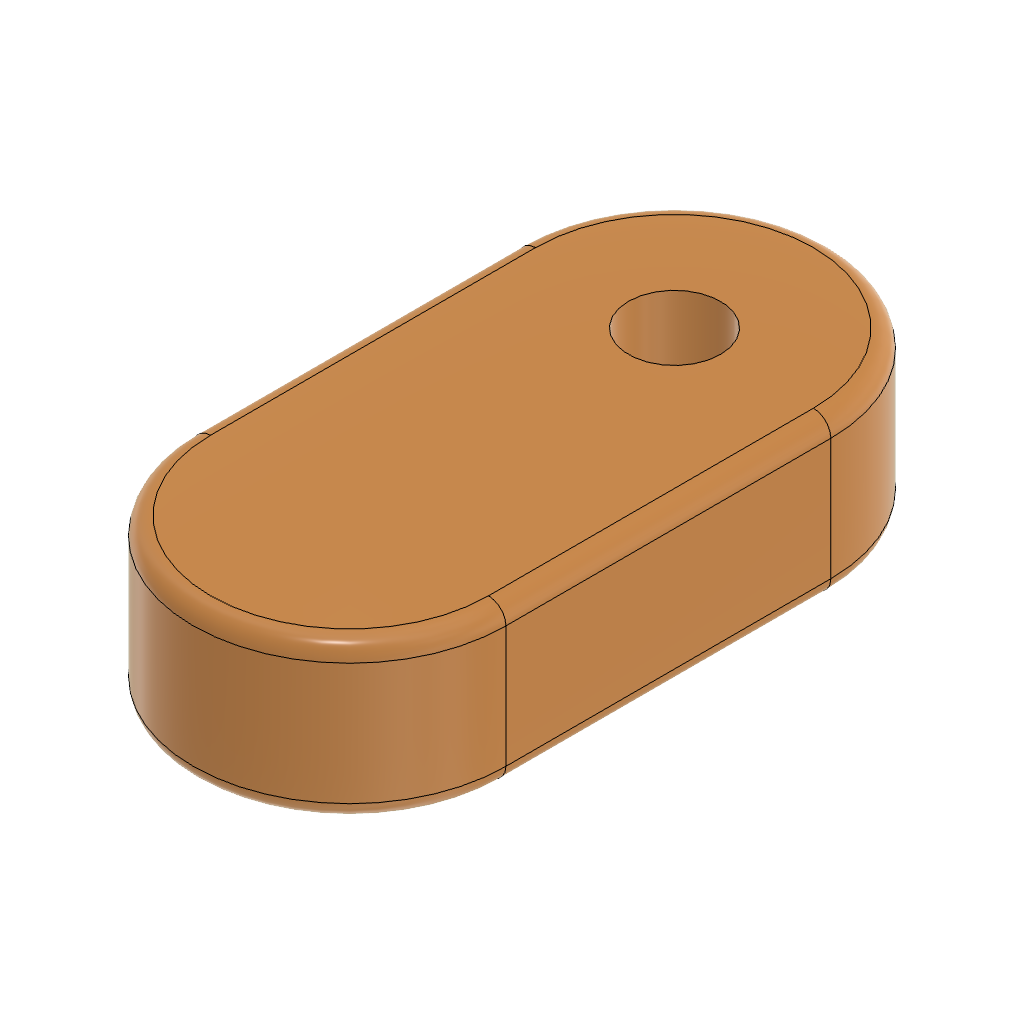
crank_outer (Autodesk Fusion 360 design; units mm, degrees)
part number: 2026-09-19-23-47-10-584
Autodesk Fusion 360 part; units mm, degrees
sketch "Sketch1" plane through (0, 0, 0) normal (0, 0, 1) x (1, 0, 0)
  line L0 (-3.85, -3.85) -> (3.85, -3.85)
  line L1 (3.85, -3.85) -> (3.85, 3.85)
  line L2 (3.85, 3.85) -> (-3.85, 3.85)
  line L3 (-3.85, 3.85) -> (-3.85, -3.85)
  line L4 (-3.85, -3.85) -> (3.85, 3.85) construction
  line L5 (3.85, -3.85) -> (-3.85, 3.85) construction
  circle A0 centre (0, 18.7) radius 9
  circle A1 centre (0, 0) radius 9
  line L6 (9, 0) -> (-9, 0)
  line L7 (-9, 0) -> (9, 0)
  line L8 (9, 0) -> (9, 18.7)
  line L9 (9, 18.7) -> (-9, 18.7)
  line L10 (-9, 18.7) -> (-9, 0)
  line L11 (-9, 0) -> (9, 18.7) construction
  line L12 (9, 0) -> (-9, 18.7) construction
  circle A2 centre (0, 18.7) radius 2.65
  point P0 (0, 18.7)
  point P1 (0, 9.35)
  dimension "d1" = 7.7
  dimension "d2" = 7.7
  dimension "d5" = 18.7
  dimension "d7" = 18
  dimension "d8" = 18
  dimension "d12" = 18
  dimension "d16" = 5.3
  dimension "d23" = 18.7
  constraint horizontal L0
  constraint perpendicular L0 L1
  constraint parallel L0 L2
  constraint parallel L1 L3
  constraint coincident L4 A1.centre
  constraint coincident L5 A1.centre
  constraint coincident A1.centre origin
  constraint coincident P0 A0.centre
  constraint horizontal L6
  constraint coincident A1 L6.end
  constraint horizontal L7
  constraint perpendicular L7 L8
  constraint parallel L7 L9
  constraint parallel L8 L10
  constraint coincident L11 P1
  constraint coincident L12 P1
  constraint vertical A1.centre A0.centre
  constraint coincident A0 L8.end
  measures "d1" distance of L1.end L2.end
  measures "d2" distance of L0.end L1.end
  measures "d5" vertical distance of A1.centre P0
  measures "d7" diameter of A0
  measures "d8" diameter of A1
  measures "d12" distance of L8.end L9.end
  measures "d16" diameter of A2
  measures "d23" distance of L6.start L8.end
extrude "Extrude2" add sketch "Sketch1" along normal blind 9 contours L0 L1 L3 A1 L6 L7 | L1 L2 L3 A1 L6 L7 | A0 A1 L8 L10 | A0 L9 A2 | A0 L9 A2 | L9 A2 | L9 A2
extrude "Extrude3" cut sketch "Sketch1" along normal blind 15 contours L9 A2 | L9 A2
sketch "Sketch2" plane through (0, 0, 9) normal (0, 0, 1) x (-1, 0, 0)
  circle A0 centre (0, -18.7) radius 2.65
  line L0 (3.85, 3.85) -> (3.85, -3.85)
  line L1 (3.85, -3.85) -> (-3.85, -3.85)
  line L2 (-3.85, -3.85) -> (-3.85, 3.85)
  line L3 (-3.85, 3.85) -> (3.85, 3.85)
  line L4 (9, -18.7) -> (9, 0)
  arc A1 (9, 0) -> (-9, 0) centre (0, 0) ccw
  line L5 (-9, 0) -> (-9, -18.7)
  arc A2 (-9, -18.7) -> (9, -18.7) centre (0, -18.7) ccw
  line L6 (-3.85, 3.85) -> (3.85, 3.85)
  line L7 (3.85, 3.85) -> (3.85, -3.85)
  line L8 (3.85, -3.85) -> (-3.85, -3.85)
  line L9 (-3.85, -3.85) -> (-3.85, 3.85)
  constraint horizontal L6
  constraint vertical L7
  constraint horizontal L8
  constraint vertical L9
  constraint coincident L0.end L1.start
  constraint coincident L2.end L3.start
extrude "Extrude4" add sketch "Sketch2" against normal blind 2 contours L0 L1 L2 L3 L6 L7 L8 L9
fillet "Fillet1" radius 1 8 edges at (9, 9.35, 9) (0, 27.7, 9) (-9, 9.35, 9) (0, -9, 9) (9, 9.35, 0) (0, 27.7, 0) (-9, 9.35, 0) (0, -9, 0)
